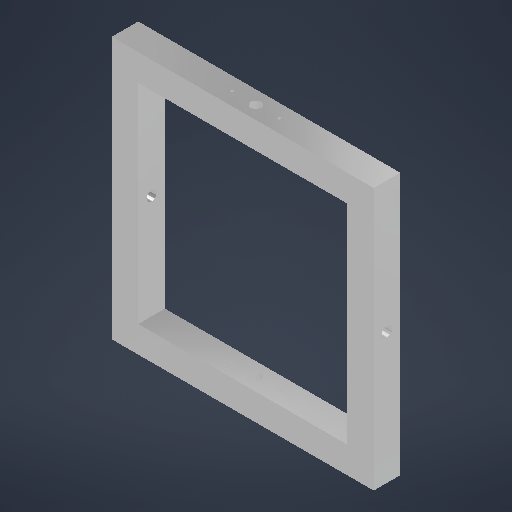
# Autodesk Inventor part: outer frame
Saved by Autodesk Inventor 2026.1 (Build 301233000, 233)
## iProperties
Created: 2025-11-10
Part Number: outer frame
Material: Aluminum 6061
Document SubType Name: Modeling
Designer: shiva
Density: 2.7 g/cm^3
Appearance: Aluminum - Flat
Mass: 12519.6 g
Surface Area: 3651.1 cm^2
Volume: 4636.89 cm^3
Author: shiva
Autodesk Inventor part; units mm, degrees
ref_plane "YZ Plane" through (0, 0, 0) normal (1, 0, 0) x (0, 1, 0)
ref_plane "XZ Plane" through (0, 0, 0) normal (0, 1, 0) x (-1, 0, 0)
ref_plane "XY Plane" through (0, 0, 0) normal (0, 0, 1) x (1, 0, 0)
sketch "Sketch4" plane through (0, 0, 0) normal (0, 0, 1) x (1, 0, 0)
  line L0 (-250, 250) -> (250, 250)
  line L1 (250, 250) -> (250, -250)
  line L2 (250, -250) -> (-250, -250)
  line L3 (-250, -250) -> (-250, 250)
  line L4 (-250, 250) -> (250, -250) construction
  line L5 (250, 250) -> (-250, -250) construction
  line L6 (-199.6, 199.2) -> (199.6, -199.2) construction
  line L7 (199.6, 199.2) -> (-199.6, -199.2) construction
  line L8 (-199.2, -199.2) -> (199.2, -199.2)
  line L9 (199.2, -199.2) -> (199.2, 199.2)
  line L10 (199.2, 199.2) -> (-199.2, 199.2)
  line L11 (-199.2, 199.2) -> (-199.2, -199.2)
  line L12 (-199.2, -199.2) -> (199.2, 199.2) construction
  line L13 (199.2, -199.2) -> (-199.2, 199.2) construction
  point P0 (0, 0)
  dimension "d12" = 500
  dimension "d13" = 500
  dimension "d19" = 500
  dimension "d20" = 398.4
  dimension "d22" = 398.4
  constraints: 28 end point, 6 midpoint, 4 parallel, 2 horizontal, 2 perpendicular
  measures "d12" distance of L1.end L2.end
  measures "d13" distance of L0.end L1.end
  measures "d19" distance of L0.start L0.end
  measures "d20" distance of L10.end L9.end
  measures "d22" distance of L8.end L9.end
extrude "Extrusion2" add sketch "Sketch4" along normal blind 50.8
sketch "Sketch5" plane through (250, -250, 0) normal (1, 0, 0) x (0, 0, -1)
  line L0 (0, 500) -> (0, 0) projected
  line L1 (0, 500) -> (-50.8, 500)
  line L2 (-50.8, 500) -> (-50.8, 0)
  line L3 (-50.8, 0) -> (0, 0)
  line L4 (0, 0) -> (0, 500)
  circle A0 centre (-25.4, 250) radius 10
  dimension "d23" = 20
  constraints: 8 end point, 2 parallel, 1 centre point, 1 horizontal, 1 perpendicular
  measures "d23" diameter of A0
sketch "Sketch7" plane through (-250, -250, 0) normal (0, -1, 0) x (1, 0, 0)
  line L0 (0, 0) -> (0, 50.8) projected
  line L1 (0, 0) -> (500, 0) projected
  line L2 (0, 50.8) -> (500, 50.8)
  line L3 (500, 50.8) -> (500, 0)
  line L4 (500, 0) -> (0, 0)
  line L5 (0, 0) -> (0, 50.8)
  circle A0 centre (250, 25.4) radius 10
  point P0 (250, 0)
  dimension "d28" = 20
  constraints: 8 end point, 2 parallel, 1 centre point, 1 horizontal, 1 perpendicular
  measures "d28" diameter of A0
extrude "Extrusion5" cut sketch "Sketch7" against normal up to surface (500 mm away) contours A0
extrude "Extrusion6" cut sketch "Sketch5" against normal through all contours A0
sketch "Sketch8" plane through (-250, 250, 0) normal (0, 1, 0) x (1, 0, 0)
  circle A0 centre (250, -25.4) radius 10 projected
  line L0 (250, -15.4) -> (250, -25.4)
  line L1 (295, -25.4) -> (205, -25.4)
  circle A1 centre (295, -25.4) radius 3
  circle A2 centre (205, -25.4) radius 3
  point P0 (250, 0)
  dimension "d33" = 90
  dimension "d34" = 6
  dimension "d35" = 6
  constraints: 4 end point, 2 centre point, 2 coincident, 1 horizontal, 1 midpoint, 1 vertical, 1 vertical alignment, 1 other
  measures "d33" distance of L1.start L1.end
  measures "d34" diameter of A1
  measures "d35" diameter of A2
extrude "Extrusion7" cut sketch "Sketch8" against normal through all contours A2 | A1
body "Solid3"
